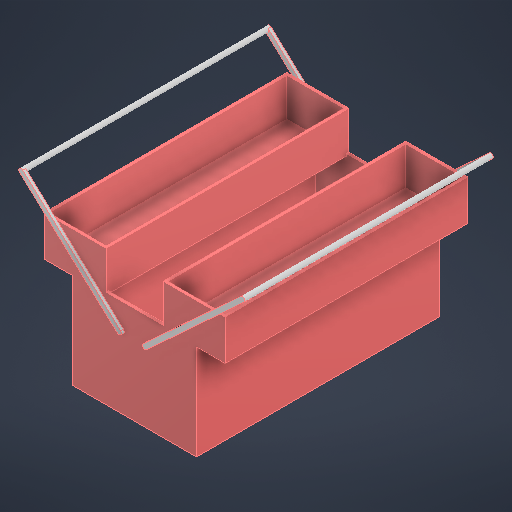
# Autodesk Inventor part: toolbox
Saved by Autodesk Inventor 2027 (Build 310192060, 192F)
## iProperties
Created: 2026-10-17
Part Number: toolbox
Material: Générique
Document SubType Name: Modeling
Designer: strei
Density: 1 g/cm^3
Appearance: Lisse - Rouge
Author: strei
Autodesk Inventor part; units mm, degrees
ref_plane "YZ Plane" through (0, 0, 0) normal (1, 0, 0) x (0, 1, 0)
ref_plane "XZ Plane" through (0, 0, 0) normal (0, 1, 0) x (-1, 0, 0)
ref_plane "XY Plane" through (0, 0, 0) normal (0, 0, 1) x (1, 0, 0)
sketch "Esquisse1" plane through (0, 0, 0) normal (0, 1, 0) x (-1, 0, 0)
  line L0 (125, 250) -> (-125, 250)
  line L1 (-125, 250) -> (-125, -250)
  line L2 (-125, -250) -> (125, -250)
  line L3 (125, -250) -> (125, 250)
  line L4 (125, 250) -> (-125, -250) construction
  line L5 (-125, 250) -> (125, -250) construction
  point P0 (0, 0)
  dimension "d0" = 250
  dimension "d1" = 500
  constraints: 12 end point, 2 midpoint, 2 parallel, 1 horizontal, 1 perpendicular
  measures "d0" distance of L2.end L1.end
  measures "d1" distance of L1.end L0.end
extrude "Extrusion1" add sketch "Esquisse1" along normal blind 200
sketch "Esquisse2" plane through (0, 200, 0) normal (0, 1, 0) x (1, 0, 0)
  line L0 (-185, -250) -> (-65, -250)
  line L1 (-65, -250) -> (-65, 250)
  line L2 (-65, 250) -> (-185, 250)
  line L3 (-185, 250) -> (-185, -250)
  line L4 (-185, -250) -> (-65, 250) construction
  line L5 (-65, -250) -> (-185, 250) construction
  line L6 (125, 250) -> (-125, 250) projected
  line L7 (-125, -250) -> (125, -250) projected
  point P0 (0, 0)
  point P1 (-125, 0)
  dimension "d5" = 120
  dimension "d6" = 125
  constraints: 12 end point, 2 collinear, 2 midpoint, 2 parallel, 1 horizontal, 1 perpendicular
  measures "d5" distance of L0.start L0.end
  measures "d6" distance of point (0, 0) point (-125, 0)
extrude "Extrusion2" add sketch "Esquisse2" along normal blind 80
mirror "Mise en miroir1" about plane through (0, 0, 0) normal (1, 0, 0) of "Extrusion2"
shell "Coque2" thickness 5 outward yes removed faces 3 at (-145, 280, -83.3333) at (-21.6667, 200, -83.3333) at (145, 280, -83.3333)
sketch "Esquisse3" plane through (-125, 0, -250) normal (1, 0, 0) x (0, 0, -1)
  line L0 (0, 200) -> (-500, 200) projected
  line L1 (0, 200) -> (-500, 200)
  line L2 (-500, 200) -> (-500, 195)
  line L3 (-500, 195) -> (0, 195)
  line L4 (0, 195) -> (0, 200)
  line L5 (-500, 200) -> (-500, 280) projected
  point P0 (-250, 0)
  dimension "d10" = 5
  constraints: 8 end point, 2 parallel, 1 collinear, 1 horizontal, 1 perpendicular
  measures "d10" distance between parallel lines of L3 L0
extrude "Extrusion3" add sketch "Esquisse3" along normal up to surface (65 mm away)
mirror "Mise en miroir2" about plane through (0, 0, 0) normal (1, 0, 0) of "Extrusion3"
sketch "Esquisse4" plane through (-130, -5, 255) normal (0, 0, 1) x (1, 0, 0)
  line L0 (102.9272, 152.1132) -> (-102.9272, 341.9131) construction
  line L1 (106.3165, 155.7892) -> (-99.5379, 345.589)
  line L2 (-106.3165, 338.2371) -> (99.5379, 148.4372)
  arc A0 (99.5379, 148.4372) -> (106.3165, 155.7892) centre (102.9272, 152.1132) ccw
  arc A1 (-99.5379, 345.589) -> (-106.3165, 338.2371) centre (-102.9272, 341.9131) ccw
  point P0 (130, 5)
  point P1 (0, 247.0131)
  point P2 (0, 200)
  dimension "d13" = 10
  dimension "d14" = 280
  constraints: 8 end point, 4 point on circle, 4 tangent, 2 centre point, 1 midpoint, 1 parallel, 1 vertical alignment
  measures "d13" diameter of A1
  measures "d14" distance of L0.start L0.end
extrude "Extrusion4" add sketch "Esquisse4" along normal blind 6
mirror "Mise en miroir3" about plane through (0, 0, 0) normal (1, 0, 0) of "Extrusion4"
mirror "Mise en miroir4" about plane through (0, 0, 0) normal (0, 0, 1) of "Extrusion4", "Mise en miroir3"
sketch "Esquisse5" plane through (178.5762, 280, 255) normal (0, 0, -1) x (-1, 0, 0)
  arc A0 (-50.9617, 60.589) -> (-57.7402, 53.2371) centre (-54.3509, 56.9131) ccw projected
  circle A1 centre (-54.3509, 56.9131) radius 5
  point P0 (178.5762, -280)
  point P1 (-57.7402, 53.2371)
  constraints: 1 centre point, 1 coincident, 1 concentric
extrude "Extrusion5" add sketch "Esquisse5" along normal up to surface (510 mm away)
mirror "Mise en miroir5" about plane through (0, 0, 0) normal (1, 0, 0) of "Extrusion5"
